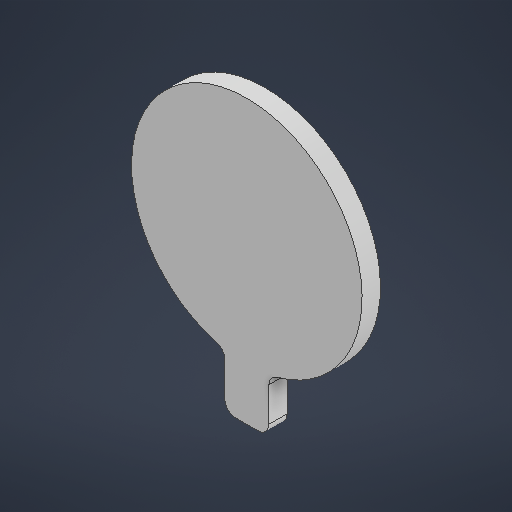
# Autodesk Inventor part: 背夹主题
Saved by Autodesk Inventor 2025 (Build 290162000, 162)
## iProperties
Created: 2025-10-16
Part Number: 背夹主题
Material: 常规
Document SubType Name: Modeling
Designer: HZD
Density: 1 g/cm^3
Appearance: 默认
Author: HZD
Autodesk Inventor part; units mm, degrees
ref_plane "YZ Plane" through (0, 0, 0) normal (1, 0, 0) x (0, 1, 0)
ref_plane "XZ Plane" through (0, 0, 0) normal (0, 1, 0) x (-1, 0, 0)
ref_plane "XY Plane" through (0, 0, 0) normal (0, 0, 1) x (1, 0, 0)
sketch "草图1" plane through (0, 0, 0) normal (0, 0, 1) x (1, 0, 0)
  line L0 (-3, -42.487) -> (3, -42.487) projected
  line L1 (-3, -26.487) -> (-3, -42.487) projected
  line L2 (3, -26.487) -> (-3, -26.487) projected
  line L3 (3, -42.487) -> (3, -26.487) projected
  arc A0 (2.9922, -45.4792) -> (5.9922, -42.4792) centre (2.9922, -42.4792) ccw projected
  line L4 (5.9922, -33.1646) -> (5.9922, -42.4792) projected
  arc A1 (8.2071, -30.2691) -> (5.9922, -33.1646) centre (8.9922, -33.1646) ccw projected
  arc A2 (8.2071, -30.2691) -> (-8.2071, -30.2691) centre (0, 0) ccw projected
  arc A3 (-5.9922, -33.1646) -> (-8.2071, -30.2691) centre (-8.9922, -33.1646) ccw projected
  line L5 (-5.9922, -42.4792) -> (-5.9922, -33.1646) projected
  arc A4 (-5.9922, -42.4792) -> (-2.9922, -45.4792) centre (-2.9922, -42.4792) ccw projected
  line L6 (2.9922, -45.4792) -> (-2.9922, -45.4792) projected
  arc A5 (4.9707, -22.4564) -> (-4.9707, -22.4564) centre (0, 0) ccw projected
  line L7 (-6.5, -26.7208) -> (-4.9707, -22.4564) projected
  arc A6 (6.5, -26.7208) -> (-6.5, -26.7208) centre (0, 0) ccw projected
  line L8 (4.9707, -22.4564) -> (6.5, -26.7208) projected
extrude "拉伸1" add sketch "草图1" along normal blind 5 contours L1 L2 L3 L0 | L6 A4 L5 A3 A2 A1 L4 A0 | A5 L7 A6 L8
